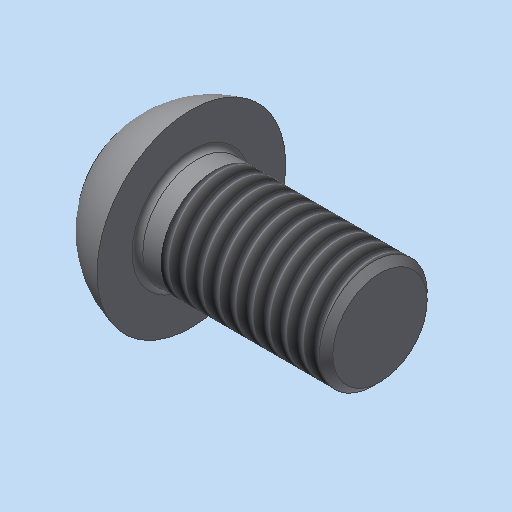
# Autodesk Inventor part: MM0861AN200_G22_323
Saved by Autodesk Inventor 2023.3 (Build 273359000, 359)
## iProperties
Part Number: MM0861AN200_G22_323
Document SubType Name: Modeling
Created: 2004-04-02
Material: xStahl_AnP_Dummymaterial
Description: =<RBPARTNOTITLE2>
Vendor: Wuerth
Designer: S.Riedelsheimer
Manufacturer: Standard
Standards Organization: Custom
Mass: 8.87127 g
Surface Area: 7.87649 cm^2
Volume: 1.1301 cm^3
Density: 7.85 g/cm^3
Appearance: RGB(178,178,178)
Control State: 0
Master: False
Checked Out: False
Shininess: 64.0
Length Units: 11269
Angle Units: 11279
Time Units: 11290
Mass Units: 11283
Length Display Precision: 3
Angle Display Precision: 2
Compacted: True
CNS_NB: Hexagon socket button head screw ISO7380-M8x16
CNS_NN: ISO 7380
CNS_NT: Hexagon socket button head screw
CNS_NBSYN: Hexagon socket button head screw ISO7380-M$D.x$L.
CNS_LINA: Hexagon socket button head screw ISO7380-M8x16
CNS_D: 8.000
CNS_D3: 6.466
CNS_P: 1.250
CNS_L: 16.000
CNS_S: 5.000
CNS_A: 2.500
CNS_DA: 9.200
CNS_DK: 14.000
CNS_K: 4.400
CNS_R: 0.400
CNS_T: 2.600
CNS_KT: DUMMY
PSOL_IDENT_0: {C:\partsolutions8\data\23d-libs\bosch_bamberg\schrauben\spezialschrauben\iso_7380.prj},183 {M=Nenng
PSOL_IDENT_1: ewinde},{VTYP=3D},{NB=Hexagon socket button head screw ISO7380-M8x16},{NN=ISO 7380},{DATE=26.11.2003
PSOL_IDENT_2: },{GEOMDATE=26.11.2003},{VERSION=v1},{LINEID=230},{LINESUBID=-1},{WBVAR=}  {NB=Hexagon socket button
PSOL_IDENT_3: head screw ISO7380-M8x16},{LINA=Hexagon socket button head screw ISO7380-M8x16},{KT=DUMMY},{IDNR=},
PSOL_IDENT_4: {D=8.000},{D3=6.466},{P=1.250},{L=16.000},{S=5.000},{A=2.500},{DA=9.200},{DK=14.000},{K=4.400},{R=0.
PSOL_IDENT_5: 400},{T=2.600}
RBPARTNOTITLE2: ISO7380 M8x14
RBPARTNOTITLE1: ISO7380 M8x14
RBPARTMADEOF: 006000814 / ISO7380-2
RBDRAWINGMISSINGSPEC: --
AnP_Kategorie: 2
RBMATERIAL: =<Material>
AnP_Material: =<Material>
RBMATNO: =<Part Number>
Density: 0.0
Volumn: 0.0
Area: 0.0
PropertySet Name: Model Information
Title: Hexagon socket button head screw ISO7380-M8x16
Author: S.Riedelsheimer
Keywords: =<RBPARTMADEOF>
Comments: =<RBSURFACE2>
Revision Number: 01
Autodesk Inventor part; units mm, degrees
sketch "Sketch_1" plane through (0, 0, 0) normal (0, 1, 0) x (-1, 0, 0)
  line L0 (0.4144, 0) -> (-16, 0)
  line L1 (-16, 0) -> (-16, 3.233)
  line L2 (-16, 3.233) -> (-15.233, 4)
  line L3 (-15.233, 4) -> (-0.4, 4)
  arc A0 (-0.4, 4) -> (0, 4.4) centre (-0.4, 4.4) ccw
  line L4 (0, 4.4) -> (0, 7)
  arc A1 (4.4, 4) -> (0, 7) centre (-1.55, 0) ccw
  line L5 (4.4, 4) -> (4.4, 2.8868)
  line L6 (4.4, 2.8868) -> (3.9132, 2.4)
  line L7 (3.9132, 2.4) -> (1.8, 2.4)
  line L8 (1.8, 2.4) -> (0.4144, 0)
  line L9 (0.4144, 0) -> (-16, 0)
  constraints: 20 end point, 4 point on circle, 2 centre point
revolve "Drehung1" add sketch "Sketch_1" angle 360 about axis through (-0.4144, 0, 0) along (1, 0, 0)
thread "Gewinde1" size "M8x1.25" class "6g" standard "ANSI Metric M Profile" length 13.5
sketch "Sketch_2" plane through (-4.4, 0, 0) normal (1, 0, 0) x (0, 0, -1)
  line L0 (-2.5, 1.4434) -> (-2.5, -1.4434)
  line L1 (-2.5, -1.4434) -> (0, -2.8868)
  line L2 (0, -2.8868) -> (2.5, -1.4434)
  line L3 (2.5, -1.4434) -> (2.5, 1.4434)
  line L4 (2.5, 1.4434) -> (0, 2.8868)
  line L5 (0, 2.8868) -> (-2.5, 1.4434)
  constraints: 12 end point
extrude "Extrusion1" cut sketch "Sketch_2" along normal blind 2.6
ref_plane "IP1_XY" through (0, 0, 0) normal (1, 0, 0) x (0, 0, -1)
ref_plane "IP1_YZ" through (0, 0, 0) normal (0, 0, -1) x (0, 1, 0)
ref_plane "IP2_XY" through (16, 0, 0) normal (1, 0, 0) x (0, 0, -1)
ref_plane "IP2_YZ" through (16, 0, 0) normal (0, 0, -1) x (0, 1, 0)
sketch "Skizze3" plane through (16, 0, 0) normal (1, 0, 0) x (0, 0, -1)
  circle A0 centre (0, 0) radius 4 projected
extrude "Extrusion2" cut sketch "Skizze3" against normal blind 2
chamfer "Fase1" distance 0.5 angle 45 1 edges at (14, 0, -4)
